Autodesk Fusion 360 part; units mm, degrees
(part 2 of 3)
sketch "web cuts" plane through (0, 0, -2.1) normal (0, 0, 1) x (1, 0, 0) in component "plate"
  line L0 (1.925, -17.125) -> (17.125, -17.125)
  line L1 (17.125, -17.125) -> (17.125, -1.925)
  line L2 (17.125, -1.925) -> (1.925, -1.925)
  line L3 (1.925, -1.925) -> (1.925, -17.125)
  line L4 (20.975, -17.125) -> (36.175, -17.125)
  line L5 (36.175, -17.125) -> (36.175, -1.925)
  line L6 (36.175, -1.925) -> (20.975, -1.925)
  line L7 (20.975, -1.925) -> (20.975, -17.125)
  line L8 (40.025, -17.125) -> (55.225, -17.125)
  line L9 (55.225, -17.125) -> (55.225, -1.925)
  line L10 (55.225, -1.925) -> (40.025, -1.925)
  line L11 (40.025, -1.925) -> (40.025, -17.125)
  line L12 (59.075, -17.125) -> (74.275, -17.125)
  line L13 (74.275, -17.125) -> (74.275, -1.925)
  line L14 (74.275, -1.925) -> (59.075, -1.925)
  line L15 (59.075, -1.925) -> (59.075, -17.125)
  line L16 (78.125, -17.125) -> (93.325, -17.125)
  line L17 (93.325, -17.125) -> (93.325, -1.925)
  line L18 (93.325, -1.925) -> (78.125, -1.925)
  line L19 (78.125, -1.925) -> (78.125, -17.125)
  line L20 (97.175, -17.125) -> (112.375, -17.125)
  line L21 (112.375, -17.125) -> (112.375, -1.925)
  line L22 (112.375, -1.925) -> (97.175, -1.925)
  line L23 (97.175, -1.925) -> (97.175, -17.125)
  line L24 (116.225, -17.125) -> (131.425, -17.125)
  line L25 (131.425, -17.125) -> (131.425, -1.925)
  line L26 (131.425, -1.925) -> (116.225, -1.925)
  line L27 (116.225, -1.925) -> (116.225, -17.125)
  line L28 (1.925, -36.175) -> (17.125, -36.175)
  line L29 (17.125, -36.175) -> (17.125, -20.975)
  line L30 (17.125, -20.975) -> (1.925, -20.975)
  line L31 (1.925, -20.975) -> (1.925, -36.175)
  line L32 (20.975, -36.175) -> (36.175, -36.175)
  line L33 (36.175, -36.175) -> (36.175, -20.975)
  line L34 (36.175, -20.975) -> (20.975, -20.975)
  line L35 (20.975, -20.975) -> (20.975, -36.175)
  line L36 (40.025, -36.175) -> (55.225, -36.175)
  line L37 (55.225, -36.175) -> (55.225, -20.975)
  line L38 (55.225, -20.975) -> (40.025, -20.975)
  line L39 (40.025, -20.975) -> (40.025, -36.175)
  line L40 (59.075, -36.175) -> (74.275, -36.175)
  line L41 (74.275, -36.175) -> (74.275, -20.975)
  line L42 (74.275, -20.975) -> (59.075, -20.975)
  line L43 (59.075, -20.975) -> (59.075, -36.175)
  line L44 (78.125, -36.175) -> (93.325, -36.175)
  line L45 (93.325, -36.175) -> (93.325, -20.975)
  line L46 (93.325, -20.975) -> (78.125, -20.975)
  line L47 (78.125, -20.975) -> (78.125, -36.175)
  line L48 (97.175, -36.175) -> (112.375, -36.175)
  line L49 (112.375, -36.175) -> (112.375, -20.975)
  line L50 (112.375, -20.975) -> (97.175, -20.975)
  line L51 (97.175, -20.975) -> (97.175, -36.175)
  line L52 (116.225, -36.175) -> (131.425, -36.175)
  line L53 (131.425, -36.175) -> (131.425, -20.975)
  line L54 (131.425, -20.975) -> (116.225, -20.975)
  line L55 (116.225, -20.975) -> (116.225, -36.175)
  line L56 (6.688, -55.225) -> (21.888, -55.225)
  line L57 (21.888, -55.225) -> (21.888, -40.025)
  line L58 (21.888, -40.025) -> (6.688, -40.025)
  line L59 (6.688, -40.025) -> (6.688, -55.225)
  line L60 (30.5, -55.225) -> (45.7, -55.225)
  line L61 (45.7, -55.225) -> (45.7, -40.025)
  line L62 (45.7, -40.025) -> (30.5, -40.025)
  line L63 (30.5, -40.025) -> (30.5, -55.225)
  line L64 (49.55, -55.225) -> (64.75, -55.225)
  line L65 (64.75, -55.225) -> (64.75, -40.025)
  line L66 (64.75, -40.025) -> (49.55, -40.025)
  line L67 (49.55, -40.025) -> (49.55, -55.225)
  line L68 (68.6, -55.225) -> (83.8, -55.225)
  line L69 (83.8, -55.225) -> (83.8, -40.025)
  line L70 (83.8, -40.025) -> (68.6, -40.025)
  line L71 (68.6, -40.025) -> (68.6, -55.225)
  line L72 (87.65, -55.225) -> (102.85, -55.225)
  line L73 (102.85, -55.225) -> (102.85, -40.025)
  line L74 (102.85, -40.025) -> (87.65, -40.025)
  line L75 (87.65, -40.025) -> (87.65, -55.225)
  line L76 (106.7, -55.225) -> (121.9, -55.225)
  line L77 (121.9, -55.225) -> (121.9, -40.025)
  line L78 (121.9, -40.025) -> (106.7, -40.025)
  line L79 (106.7, -40.025) -> (106.7, -55.225)
  line L80 (9.069, -74.275) -> (24.269, -74.275)
  line L81 (24.269, -74.275) -> (24.269, -59.075)
  line L82 (24.269, -59.075) -> (9.069, -59.075)
  line L83 (9.069, -59.075) -> (9.069, -74.275)
  line L84 (35.263, -74.275) -> (50.463, -74.275)
  line L85 (50.463, -74.275) -> (50.463, -59.075)
  line L86 (50.463, -59.075) -> (35.263, -59.075)
  line L87 (35.263, -59.075) -> (35.263, -74.275)
  line L88 (54.313, -74.275) -> (69.513, -74.275)
  line L89 (69.513, -74.275) -> (69.513, -59.075)
  line L90 (69.513, -59.075) -> (54.313, -59.075)
  line L91 (54.313, -59.075) -> (54.313, -74.275)
  line L92 (73.363, -74.275) -> (88.563, -74.275)
  line L93 (88.563, -74.275) -> (88.563, -59.075)
  line L94 (88.563, -59.075) -> (73.363, -59.075)
  line L95 (73.363, -59.075) -> (73.363, -74.275)
  line L96 (92.413, -74.275) -> (107.613, -74.275)
  line L97 (107.613, -74.275) -> (107.613, -59.075)
  line L98 (107.613, -59.075) -> (92.413, -59.075)
  line L99 (92.413, -59.075) -> (92.413, -74.275)
  line L100 (111.462, -74.275) -> (126.662, -74.275)
  line L101 (126.662, -74.275) -> (126.662, -59.075)
  line L102 (126.662, -59.075) -> (111.462, -59.075)
  line L103 (111.462, -59.075) -> (111.462, -74.275)
  line L104 (13.831, -93.325) -> (29.031, -93.325)
  line L105 (29.031, -93.325) -> (29.031, -78.125)
  line L106 (29.031, -78.125) -> (13.831, -78.125)
  line L107 (13.831, -78.125) -> (13.831, -93.325)
  line L108 (4.993, -94.925) -> (13.993, -94.925)
  line L109 (13.993, -94.925) -> (13.993, -77.525)
  line L110 (13.993, -77.525) -> (4.993, -77.525)
  line L111 (4.993, -77.525) -> (4.993, -94.925)
  line L112 (28.869, -94.925) -> (37.869, -94.925)
  line L113 (37.869, -94.925) -> (37.869, -77.525)
  line L114 (37.869, -77.525) -> (28.869, -77.525)
  line L115 (28.869, -77.525) -> (28.869, -94.925)
  line L116 (44.788, -93.325) -> (59.988, -93.325)
  line L117 (59.988, -93.325) -> (59.988, -78.125)
  line L118 (59.988, -78.125) -> (44.788, -78.125)
  line L119 (44.788, -78.125) -> (44.788, -93.325)
  line L120 (63.838, -93.325) -> (79.038, -93.325)
  line L121 (79.038, -93.325) -> (79.038, -78.125)
  line L122 (79.038, -78.125) -> (63.838, -78.125)
  line L123 (63.838, -78.125) -> (63.838, -93.325)
  line L124 (82.887, -93.325) -> (98.087, -93.325)
  line L125 (98.087, -93.325) -> (98.087, -78.125)
  line L126 (98.087, -78.125) -> (82.887, -78.125)
  line L127 (82.887, -78.125) -> (82.887, -93.325)
  line L128 (101.938, -93.325) -> (117.138, -93.325)
  line L129 (117.138, -93.325) -> (117.138, -78.125)
  line L130 (117.138, -78.125) -> (101.938, -78.125)
  line L131 (101.938, -78.125) -> (101.938, -93.325)
  line L132 (120.988, -93.325) -> (136.188, -93.325)
  line L133 (136.188, -93.325) -> (136.188, -78.125)
  line L134 (136.188, -78.125) -> (120.988, -78.125)
  line L135 (120.988, -78.125) -> (120.988, -93.325)
  line L136 (13.831, -112.375) -> (29.031, -112.375)
  line L137 (29.031, -112.375) -> (29.031, -97.175)
  line L138 (29.031, -97.175) -> (13.831, -97.175)
  line L139 (13.831, -97.175) -> (13.831, -112.375)
  line L140 (37.644, -112.375) -> (52.844, -112.375)
  line L141 (52.844, -112.375) -> (52.844, -97.175)
  line L142 (52.844, -97.175) -> (37.644, -97.175)
  line L143 (37.644, -97.175) -> (37.644, -112.375)
  line L144 (61.456, -112.375) -> (76.656, -112.375)
  line L145 (76.656, -112.375) -> (76.656, -97.175)
  line L146 (76.656, -97.175) -> (61.456, -97.175)
  line L147 (61.456, -97.175) -> (61.456, -112.375)
  line L148 (82.887, -112.375) -> (98.087, -112.375)
  line L149 (98.087, -112.375) -> (98.087, -97.175)
  line L150 (98.087, -97.175) -> (82.887, -97.175)
  line L151 (82.887, -97.175) -> (82.887, -112.375)
  line L152 (101.938, -112.375) -> (117.138, -112.375)
  line L153 (117.138, -112.375) -> (117.138, -97.175)
  line L154 (117.138, -97.175) -> (101.938, -97.175)
  line L155 (101.938, -97.175) -> (101.938, -112.375)
  line L156 (120.988, -112.375) -> (136.188, -112.375)
  line L157 (136.188, -112.375) -> (136.188, -97.175)
  line L158 (136.188, -97.175) -> (120.988, -97.175)
  line L159 (120.988, -97.175) -> (120.988, -112.375)
  line L160 (145.325, -36.895) -> (154.125, -36.895)
  line L161 (162.125, -28.895) -> (162.125, 5)
  line L162 (154.125, 13) -> (145.325, 13)
  line L163 (137.325, 5) -> (137.325, -28.895)
  arc A0 (154.125, -36.895) -> (162.125, -28.895) centre (154.125, -28.895) ccw
  arc A1 (162.125, 5) -> (154.125, 13) centre (154.125, 5) ccw
  arc A2 (145.325, 13) -> (137.325, 5) centre (145.325, 5) ccw
  arc A3 (137.325, -28.895) -> (145.325, -36.895) centre (145.325, -28.895) ccw
  circle A4 centre (16, -19.05) radius 3.3
  circle A5 centre (56.5, -19.05) radius 3.3
  circle A6 centre (100.5, -19.05) radius 3.3
  circle A7 centre (132, -19.05) radius 3.3
  circle A8 centre (17, -95.25) radius 3.3
  circle A9 centre (58.5, -95.25) radius 3.3
  circle A10 centre (99.5, -95.25) radius 3.3
  circle A11 centre (142.5, -95.25) radius 3.3
  dimension "d2473" = 6.6
  dimension "d2474" = 6.6
  dimension "d2475" = 6.6
  dimension "d2476" = 6.6
  dimension "d2477" = 6.6
  dimension "d2478" = 6.6
  dimension "d2479" = 6.6
  dimension "d2480" = 6.6
  constraint coincident L0.end L1.start
  constraint coincident L1.end L2.start
  constraint coincident L2.end L3.start
  constraint coincident L0.start L3.end
  constraint coincident L4.end L5.start
  constraint coincident L5.end L6.start
  constraint coincident L6.end L7.start
  constraint coincident L4.start L7.end
  constraint coincident L8.end L9.start
  constraint coincident L9.end L10.start
  constraint coincident L10.end L11.start
  constraint coincident L8.start L11.end
  constraint coincident L12.end L13.start
  constraint coincident L13.end L14.start
  constraint coincident L14.end L15.start
  constraint coincident L12.start L15.end
  constraint coincident L16.end L17.start
  constraint coincident L17.end L18.start
  constraint coincident L18.end L19.start
  constraint coincident L16.start L19.end
  constraint coincident L20.end L21.start
  constraint coincident L21.end L22.start
  constraint coincident L22.end L23.start
  constraint coincident L20.start L23.end
  constraint coincident L24.end L25.start
  constraint coincident L25.end L26.start
  constraint coincident L26.end L27.start
  constraint coincident L24.start L27.end
  constraint coincident L28.end L29.start
  constraint coincident L29.end L30.start
  constraint coincident L30.end L31.start
  constraint coincident L28.start L31.end
  constraint coincident L32.end L33.start
  constraint coincident L33.end L34.start
  constraint coincident L34.end L35.start
  constraint coincident L32.start L35.end
  constraint coincident L36.end L37.start
  constraint coincident L37.end L38.start
  constraint coincident L38.end L39.start
  constraint coincident L36.start L39.end
  constraint coincident L40.end L41.start
  constraint coincident L41.end L42.start
  constraint coincident L42.end L43.start
  constraint coincident L40.start L43.end
  constraint coincident L44.end L45.start
  constraint coincident L45.end L46.start
  constraint coincident L46.end L47.start
  constraint coincident L44.start L47.end
  constraint coincident L48.end L49.start
  constraint coincident L49.end L50.start
  constraint coincident L50.end L51.start
  constraint coincident L48.start L51.end
  constraint coincident L52.end L53.start
  constraint coincident L53.end L54.start
  constraint coincident L54.end L55.start
  constraint coincident L52.start L55.end
  constraint coincident L56.end L57.start
  constraint coincident L57.end L58.start
  constraint coincident L58.end L59.start
  constraint coincident L56.start L59.end
  constraint coincident L60.end L61.start
  constraint coincident L61.end L62.start
  constraint coincident L62.end L63.start
  constraint coincident L60.start L63.end
  constraint coincident L64.end L65.start
  constraint coincident L65.end L66.start
  constraint coincident L66.end L67.start
  constraint coincident L64.start L67.end
  constraint coincident L68.end L69.start
  constraint coincident L69.end L70.start
  constraint coincident L70.end L71.start
  constraint coincident L68.start L71.end
  constraint coincident L72.end L73.start
  constraint coincident L73.end L74.start
  constraint coincident L74.end L75.start
  constraint coincident L72.start L75.end
  constraint coincident L76.end L77.start
  constraint coincident L77.end L78.start
  constraint coincident L78.end L79.start
  constraint coincident L76.start L79.end
  constraint coincident L80.end L81.start
  constraint coincident L81.end L82.start
  constraint coincident L82.end L83.start
  constraint coincident L80.start L83.end
  constraint coincident L84.end L85.start
  constraint coincident L85.end L86.start
  constraint coincident L86.end L87.start
  constraint coincident L84.start L87.end
  constraint coincident L88.end L89.start
  constraint coincident L89.end L90.start
  constraint coincident L90.end L91.start
  constraint coincident L88.start L91.end
  constraint coincident L92.end L93.start
  constraint coincident L93.end L94.start
  constraint coincident L94.end L95.start
  constraint coincident L92.start L95.end
  constraint coincident L96.end L97.start
  constraint coincident L97.end L98.start
  constraint coincident L98.end L99.start
  constraint coincident L96.start L99.end
  constraint coincident L100.end L101.start
  constraint coincident L101.end L102.start
  constraint coincident L102.end L103.start
  constraint coincident L100.start L103.end
  constraint coincident L104.end L105.start
  constraint coincident L105.end L106.start
  constraint coincident L106.end L107.start
  constraint coincident L104.start L107.end
  constraint coincident L108.end L109.start
  constraint coincident L109.end L110.start
  constraint coincident L110.end L111.start
  constraint coincident L108.start L111.end
  constraint coincident L112.end L113.start
  constraint coincident L113.end L114.start
  constraint coincident L114.end L115.start
  constraint coincident L112.start L115.end
  constraint coincident L116.end L117.start
  constraint coincident L117.end L118.start
  constraint coincident L118.end L119.start
  constraint coincident L116.start L119.end
  constraint coincident L120.end L121.start
  constraint coincident L121.end L122.start
  constraint coincident L122.end L123.start
  constraint coincident L120.start L123.end
  constraint coincident L124.end L125.start
  constraint coincident L125.end L126.start
  constraint coincident L126.end L127.start
  constraint coincident L124.start L127.end
  constraint coincident L128.end L129.start
  constraint coincident L129.end L130.start
  constraint coincident L130.end L131.start
  constraint coincident L128.start L131.end
  constraint coincident L132.end L133.start
  constraint coincident L133.end L134.start
  constraint coincident L134.end L135.start
  constraint coincident L132.start L135.end
  constraint coincident L136.end L137.start
  constraint coincident L137.end L138.start
  constraint coincident L138.end L139.start
  constraint coincident L136.start L139.end
  constraint coincident L140.end L141.start
  constraint coincident L141.end L142.start
  constraint coincident L142.end L143.start
  constraint coincident L140.start L143.end
  constraint coincident L144.end L145.start
  constraint coincident L145.end L146.start
  constraint coincident L146.end L147.start
  constraint coincident L144.start L147.end
  constraint coincident L148.end L149.start
  constraint coincident L149.end L150.start
  constraint coincident L150.end L151.start
  constraint coincident L148.start L151.end
  constraint coincident L152.end L153.start
  constraint coincident L153.end L154.start
  constraint coincident L154.end L155.start
  constraint coincident L152.start L155.end
  constraint coincident L156.end L157.start
  constraint coincident L157.end L158.start
  constraint coincident L158.end L159.start
  constraint coincident L156.start L159.end
  measures "d2473" diameter of A4
  measures "d2474" diameter of A5
  measures "d2475" diameter of A6
  measures "d2476" diameter of A7
  measures "d2477" diameter of A8
  measures "d2478" diameter of A9
  measures "d2479" diameter of A10
  measures "d2480" diameter of A11
extrude "Extrude4'" cut sketch "web cuts" along normal blind 2.2 bodies 3 in component "plate"
combine "Combine1" operation add target body 2 tool bodies 3 in component "plate"
sketch "plate bosses" plane through (0, 0, 0) normal (0, 0, 1) x (1, 0, 0) in component "plate"
  circle A0 centre (-5.0104, -119.3104) radius 2.8
  circle A1 centre (160.1354, -119.3104) radius 2.8
  circle A2 centre (49.2083, 13.5) radius 2.8
  circle A3 centre (49.2083, -121.8) radius 2.8
  circle A4 centre (105.9167, 13.5) radius 2.8
  circle A5 centre (105.9167, -121.8) radius 2.8
  circle A6 centre (-7.5, -54.15) radius 2.8
  circle A7 centre (162.625, -54.15) radius 2.8
  circle A8 centre (19.1438, 13.5) radius 2.8
  circle A9 centre (-7.5, -13.1438) radius 2.8
  dimension "d2483" = 5.6
  dimension "d2484" = 5.6
  dimension "d2485" = 5.6
  dimension "d2486" = 5.6
  dimension "d2487" = 5.6
  dimension "d2488" = 5.6
  dimension "d2489" = 5.6
  dimension "d2490" = 5.6
  dimension "d2491" = 5.6
  dimension "d2492" = 5.6
  measures "d2483" diameter of A0
  measures "d2484" diameter of A1
  measures "d2485" diameter of A2
  measures "d2486" diameter of A3
  measures "d2487" diameter of A4
  measures "d2488" diameter of A5
  measures "d2489" diameter of A6
  measures "d2490" diameter of A7
  measures "d2491" diameter of A8
  measures "d2492" diameter of A9
extrude "Extrude5'" add sketch "plate bosses" against normal blind 3 bodies 2 in component "plate"
sketch "inserts" plane through (0, 0, 0) normal (0, 0, 1) x (1, 0, 0) in component "plate"
  circle A0 centre (-5.0104, -119.3104) radius 1.6
  circle A1 centre (160.1354, -119.3104) radius 1.6
  circle A2 centre (49.2083, 13.5) radius 1.6
  circle A3 centre (49.2083, -121.8) radius 1.6
  circle A4 centre (105.9167, 13.5) radius 1.6
  circle A5 centre (105.9167, -121.8) radius 1.6
  circle A6 centre (-7.5, -54.15) radius 1.6
  circle A7 centre (162.625, -54.15) radius 1.6
  circle A8 centre (19.1438, 13.5) radius 1.6
  circle A9 centre (-7.5, -13.1438) radius 1.6
  dimension "d2495" = 3.2
  dimension "d2496" = 3.2
  dimension "d2497" = 3.2
  dimension "d2498" = 3.2
  dimension "d2499" = 3.2
  dimension "d2500" = 3.2
  dimension "d2501" = 3.2
  dimension "d2502" = 3.2
  dimension "d2503" = 3.2
  dimension "d2504" = 3.2
  measures "d2495" diameter of A0
  measures "d2496" diameter of A1
  measures "d2497" diameter of A2
  measures "d2498" diameter of A3
  measures "d2499" diameter of A4
  measures "d2500" diameter of A5
  measures "d2501" diameter of A6
  measures "d2502" diameter of A7
  measures "d2503" diameter of A8
  measures "d2504" diameter of A9
extrude "Extrude6'" cut sketch "inserts" against normal blind 3.01 bodies 2 in component "plate"
sketch "rim" plane through (0, 0, 0) normal (0, 0, 1) x (1, 0, 0) in component "wheel"
  spline S0 degree 5 poles (16.6, 4) (16.6, 4.0196) (16.5988, 4.0588) (16.5932, 4.1175) (16.5787, 4.1954) (16.5497, 4.2915) (16.5116, 4.3858) (16.4664, 4.4782) (16.416, 4.5686) (16.3623, 4.6574) (16.3071, 4.7453) (16.252, 4.8329) (16.1989, 4.9209) (16.1495, 5.01) (16.106, 5.1006) (16.0704, 5.1928) (16.0444, 5.2866) (16.0293, 5.3818) (16.0255, 5.4781) (16.0327, 5.5751) (16.0497, 5.6725) (16.0747, 5.7698) (16.1057, 5.8669) (16.1406, 5.9636) (16.1776, 6.0602) (16.2146, 6.1572) (16.25, 6.2547) (16.2817, 6.3532) (16.3081, 6.4526) (16.327, 6.5526) (16.3367, 6.6525) (16.3355, 6.7516) (16.3225, 6.8489) (16.2973, 6.9439) (16.2604, 7.0358) (16.2133, 7.1244) (16.1575, 7.2095) (16.0951, 7.2913) (16.0281, 7.3701) (15.9581, 7.4467) (15.8868, 7.5221) (15.8157, 7.5973) (15.7464, 7.6733) (15.6806, 7.751) (15.6203, 7.8314) (15.5673, 7.9149) (15.5235, 8.0018) (15.4901, 8.0922) (15.4677, 8.1859) (15.4558, 8.2825) (15.4534, 8.3813) (15.459, 8.4817) (15.4705, 8.5829) (15.4859, 8.6846) (15.5032, 8.7865) (15.5207, 8.8888) (15.5363, 8.9914) (15.5482, 9.0942) (15.5547, 9.1969) (15.5537, 9.2986) (15.5437, 9.3985) (15.5233, 9.4954) (15.4915, 9.5884) (15.4482, 9.6766) (15.3942, 9.7596) (15.3306, 9.8372) (15.2593, 9.9098) (15.1822, 9.9779) (15.1011, 10.0421) (15.0175, 10.1036) (14.9328, 10.1636) (14.8484, 10.2235) (14.7656, 10.2845) (14.6859, 10.3479) (14.6111, 10.415) (14.5429, 10.4865) (14.483, 10.5632) (14.4326, 10.6453) (14.3923, 10.7329) (14.3618, 10.8253) (14.3402, 10.9218) (14.326, 11.0213) (14.3176, 11.1228) (14.3128, 11.2255) (14.31, 11.3289) (14.3071, 11.4327) (14.3024, 11.5363) (14.2941, 11.6395) (14.2803, 11.7414) (14.2596, 11.841) (14.2303, 11.937) (14.1913, 12.0281) (14.142, 12.113) (14.0824, 12.1911) (14.0132, 12.262) (13.9357, 12.3258) (13.8516, 12.3831) (13.7627, 12.4347) (13.6706, 12.4819) (13.5766, 12.5259) (13.4819, 12.5683) (13.3874, 12.6105) (13.2943, 12.6542) (13.2038, 12.7009) (13.1173, 12.752) (13.0364, 12.8089) (12.9627, 12.8724) (12.8972, 12.9431) (12.8406, 13.0212) (12.7927, 13.1059) (12.7527, 13.1962) (12.7194, 13.291) (12.6913, 13.3889) (12.6666, 13.4888) (12.6436, 13.5897) (12.6206, 13.6908) (12.5957, 13.7916) (12.5674, 13.8911) (12.5341, 13.9884) (12.4943, 14.0821) (12.4469, 14.1705) (12.3909, 14.2522) (12.326, 14.326) (12.2522, 14.3909) (12.1705, 14.4469) (12.0821, 14.4943) (11.9884, 14.5341) (11.8911, 14.5674) (11.7916, 14.5957) (11.6908, 14.6206) (11.5897, 14.6436) (11.4888, 14.6666) (11.3889, 14.6913) (11.291, 14.7194) (11.1962, 14.7527) (11.1059, 14.7927) (11.0212, 14.8406) (10.9431, 14.8972) (10.8724, 14.9627) (10.8089, 15.0364) (10.752, 15.1173) (10.7009, 15.2038) (10.6542, 15.2943) (10.6105, 15.3874) (10.5683, 15.4819) (10.5259, 15.5766) (10.4819, 15.6706) (10.4347, 15.7627) (10.3831, 15.8516) (10.3258, 15.9357) (10.262, 16.0132) (10.1911, 16.0824) (10.113, 16.142) (10.0281, 16.1913) (9.937, 16.2303) (9.841, 16.2596) (9.7414, 16.2803) (9.6395, 16.2941) (9.5363, 16.3024) (9.4327, 16.3071) (9.3289, 16.31) (9.2255, 16.3128) (9.1228, 16.3176) (9.0213, 16.326) (8.9218, 16.3402) (8.8253, 16.3618) (8.7329, 16.3923) (8.6453, 16.4326) (8.5632, 16.483) (8.4865, 16.5429) (8.415, 16.6111) (8.3479, 16.6859) (8.2845, 16.7656) (8.2235, 16.8484) (8.1636, 16.9328) (8.1036, 17.0175) (8.0421, 17.1011) (7.9779, 17.1822) (7.9098, 17.2593) (7.8372, 17.3306) (7.7596, 17.3942) (7.6766, 17.4482) (7.5884, 17.4915) (7.4954, 17.5233) (7.3985, 17.5437) (7.2986, 17.5537) (7.1969, 17.5547) (7.0942, 17.5482) (6.9914, 17.5363) (6.8888, 17.5207) (6.7865, 17.5032) (6.6846, 17.4859) (6.5829, 17.4705) (6.4817, 17.459) (6.3813, 17.4534) (6.2825, 17.4558) (6.1859, 17.4677) (6.0922, 17.4901) (6.0018, 17.5235) (5.9149, 17.5673) (5.8314, 17.6203) (5.751, 17.6806) (5.6733, 17.7464) (5.5973, 17.8157) (5.5221, 17.8868) (5.4467, 17.9581) (5.3701, 18.0281) (5.2913, 18.0951) (5.2095, 18.1575) (5.1244, 18.2133) (5.0358, 18.2604) (4.9439, 18.2973) (4.8489, 18.3225) (4.7516, 18.3355) (4.6525, 18.3367) (4.5526, 18.327) (4.4526, 18.3081) (4.3532, 18.2817) (4.2547, 18.25) (4.1572, 18.2146) (4.0602, 18.1776) (3.9636, 18.1406) (3.8669, 18.1057) (3.7698, 18.0747) (3.6725, 18.0497) (3.5751, 18.0327) (3.4781, 18.0255) (3.3818, 18.0293) (3.2866, 18.0444) (3.1928, 18.0704) (3.1006, 18.106) (3.01, 18.1495) (2.9209, 18.1989) (2.8329, 18.252) (2.7453, 18.3071) (2.6574, 18.3623) (2.5686, 18.416) (2.4782, 18.4664) (2.3858, 18.5116) (2.2915, 18.5497) (2.1954, 18.5787) (2.098, 18.5969) (2, 18.6031) (1.902, 18.5969) (1.8046, 18.5787) (1.7085, 18.5497) (1.6142, 18.5116) (1.5218, 18.4664) (1.4314, 18.416) (1.3426, 18.3623) (1.2547, 18.3071) (1.1671, 18.252) (1.0791, 18.1989) (0.99, 18.1495) (0.8994, 18.106) (0.8072, 18.0704) (0.7134, 18.0444) (0.6182, 18.0293) (0.5219, 18.0255) (0.4249, 18.0327) (0.3275, 18.0497) (0.2302, 18.0747) (0.1331, 18.1057) (0.0364, 18.1406) (-0.0602, 18.1776) (-0.1572, 18.2146) (-0.2547, 18.25) (-0.3532, 18.2817) (-0.4526, 18.3081) (-0.5526, 18.327) (-0.6525, 18.3367) (-0.7516, 18.3355) (-0.8489, 18.3225) (-0.9439, 18.2973) (-1.0358, 18.2604) (-1.1244, 18.2133) (-1.2095, 18.1575) (-1.2913, 18.0951) (-1.3701, 18.0281) (-1.4467, 17.9581) (-1.5221, 17.8868) (-1.5973, 17.8157) (-1.6733, 17.7464) (-1.751, 17.6806) (-1.8314, 17.6203) (-1.9149, 17.5673) (-2.0018, 17.5235) (-2.0922, 17.4901) (-2.1859, 17.4677) (-2.2825, 17.4558) (-2.3813, 17.4534) (-2.4817, 17.459) (-2.5829, 17.4705) (-2.6846, 17.4859) (-2.7865, 17.5032) (-2.8888, 17.5207) (-2.9914, 17.5363) (-3.0942, 17.5482) (-3.1969, 17.5547) (-3.2986, 17.5537) (-3.3985, 17.5437) (-3.4954, 17.5233) (-3.5884, 17.4915) (-3.6766, 17.4482) (-3.7596, 17.3942) (-3.8372, 17.3306) (-3.9098, 17.2593) (-3.9779, 17.1822) (-4.0421, 17.1011) (-4.1036, 17.0175) (-4.1636, 16.9328) (-4.2235, 16.8484) (-4.2845, 16.7656) (-4.3479, 16.6859) (-4.415, 16.6111) (-4.4865, 16.5429) (-4.5632, 16.483) (-4.6453, 16.4326) (-4.7329, 16.3923) (-4.8253, 16.3618) (-4.9218, 16.3402) (-5.0213, 16.326) (-5.1228, 16.3176) (-5.2255, 16.3128) (-5.3289, 16.31) (-5.4327, 16.3071) (-5.5363, 16.3024) (-5.6395, 16.2941) (-5.7414, 16.2803) (-5.841, 16.2596) (-5.937, 16.2303) (-6.0281, 16.1913) (-6.113, 16.142) (-6.1911, 16.0824) (-6.262, 16.0132) (-6.3258, 15.9357) (-6.3831, 15.8516) (-6.4347, 15.7627) (-6.4819, 15.6706) (-6.5259, 15.5766) (-6.5683, 15.4819) (-6.6105, 15.3874) (-6.6542, 15.2943) (-6.7009, 15.2038) (-6.752, 15.1173) (-6.8089, 15.0364) (-6.8724, 14.9627) (-6.9431, 14.8972) (-7.0212, 14.8406) (-7.1059, 14.7927) (-7.1962, 14.7527) (-7.291, 14.7194) (-7.3889, 14.6913) (-7.4888, 14.6666) (-7.5897, 14.6436) (-7.6908, 14.6206) (-7.7916, 14.5957) (-7.8911, 14.5674) (-7.9884, 14.5341) (-8.0821, 14.4943) (-8.1705, 14.4469) (-8.2522, 14.3909) (-8.326, 14.326) (-8.3909, 14.2522) (-8.4469, 14.1705) (-8.4943, 14.0821) (-8.5341, 13.9884) (-8.5674, 13.8911) (-8.5957, 13.7916) (-8.6206, 13.6908) (-8.6436, 13.5897) (-8.6666, 13.4888) (-8.6913, 13.3889) (-8.7194, 13.291) (-8.7527, 13.1962) (-8.7927, 13.1059) (-8.8406, 13.0212) (-8.8972, 12.9431) (-8.9627, 12.8724) (-9.0364, 12.8089) (-9.1173, 12.752) (-9.2038, 12.7009) (-9.2943, 12.6542) (-9.3874, 12.6105) (-9.4819, 12.5683) (-9.5766, 12.5259) (-9.6706, 12.4819) (-9.7627, 12.4347) (-9.8516, 12.3831) (-9.9357, 12.3258) (-10.0132, 12.262) (-10.0824, 12.1911) (-10.142, 12.113) (-10.1913, 12.0281) (-10.2303, 11.937) (-10.2596, 11.841) (-10.2803, 11.7414) (-10.2941, 11.6395) (-10.3024, 11.5363) (-10.3071, 11.4327) (-10.31, 11.3289) (-10.3128, 11.2255) (-10.3176, 11.1228) (-10.326, 11.0213) (-10.3402, 10.9218) (-10.3618, 10.8253) (-10.3923, 10.7329) (-10.4326, 10.6453) (-10.483, 10.5632) (-10.5429, 10.4865) (-10.6111, 10.415) (-10.6859, 10.3479) (-10.7656, 10.2845) (-10.8484, 10.2235) (-10.9328, 10.1636) (-11.0175, 10.1036) (-11.1011, 10.0421) (-11.1822, 9.9779) (-11.2593, 9.9098) (-11.3306, 9.8372) (-11.3942, 9.7596) (-11.4482, 9.6766) (-11.4915, 9.5884) (-11.5233, 9.4954) (-11.5437, 9.3985) (-11.5537, 9.2986) (-11.5547, 9.1969) (-11.5482, 9.0942) (-11.5363, 8.9914) (-11.5207, 8.8888) (-11.5032, 8.7865) (-11.4859, 8.6846) (-11.4705, 8.5829) (-11.459, 8.4817) (-11.4534, 8.3813) (-11.4558, 8.2825) (-11.4677, 8.1859) (-11.4901, 8.0922) (-11.5235, 8.0018) (-11.5673, 7.9149) (-11.6203, 7.8314) (-11.6806, 7.751) (-11.7464, 7.6733) (-11.8157, 7.5973) (-11.8868, 7.5221) (-11.9581, 7.4467) (-12.0281, 7.3701) (-12.0951, 7.2913) (-12.1575, 7.2095) (-12.2133, 7.1244) (-12.2604, 7.0358) (-12.2973, 6.9439) (-12.3225, 6.8489) (-12.3355, 6.7516) (-12.3367, 6.6525) (-12.327, 6.5526) (-12.3081, 6.4526) (-12.2817, 6.3532) (-12.25, 6.2547) (-12.2146, 6.1572) (-12.1776, 6.0602) (-12.1406, 5.9636) (-12.1057, 5.8669) (-12.0747, 5.7698) (-12.0497, 5.6725) (-12.0327, 5.5751) (-12.0255, 5.4781) (-12.0293, 5.3818) (-12.0444, 5.2866) (-12.0704, 5.1928) (-12.106, 5.1006) (-12.1495, 5.01) (-12.1989, 4.9209) (-12.252, 4.8329) (-12.3071, 4.7453) (-12.3623, 4.6574) (-12.416, 4.5686) (-12.4664, 4.4782) (-12.5116, 4.3858) (-12.5497, 4.2915) (-12.5787, 4.1954) (-12.5969, 4.098) (-12.6031, 4) (-12.5969, 3.902) (-12.5787, 3.8046) (-12.5497, 3.7085) (-12.5116, 3.6142) (-12.4664, 3.5218) (-12.416, 3.4314) (-12.3623, 3.3426) (-12.3071, 3.2547) (-12.252, 3.1671) (-12.1989, 3.0791) (-12.1495, 2.99) (-12.106, 2.8994) (-12.0704, 2.8072) (-12.0444, 2.7134) (-12.0293, 2.6182) (-12.0255, 2.5219) (-12.0327, 2.4249) (-12.0497, 2.3275) (-12.0747, 2.2302) (-12.1057, 2.1331) (-12.1406, 2.0364) (-12.1776, 1.9398) (-12.2146, 1.8428) (-12.25, 1.7453) (-12.2817, 1.6468) (-12.3081, 1.5474) (-12.327, 1.4474) (-12.3367, 1.3475) (-12.3355, 1.2484) (-12.3225, 1.1511) (-12.2973, 1.0561) (-12.2604, 0.9642) (-12.2133, 0.8756) (-12.1575, 0.7905) (-12.0951, 0.7087) (-12.0281, 0.6299) (-11.9581, 0.5533) (-11.8868, 0.4779) (-11.8157, 0.4027) (-11.7464, 0.3267) (-11.6806, 0.249) (-11.6203, 0.1686) (-11.5673, 0.0851) (-11.5235, -0.0018) (-11.4901, -0.0922) (-11.4677, -0.1859) (-11.4558, -0.2825) (-11.4534, -0.3813) (-11.459, -0.4817) (-11.4705, -0.5829) (-11.4859, -0.6846) (-11.5032, -0.7865) (-11.5207, -0.8888) (-11.5363, -0.9914) (-11.5482, -1.0942) (-11.5547, -1.1969) (-11.5537, -1.2986) (-11.5437, -1.3985) (-11.5233, -1.4954) (-11.4915, -1.5884) (-11.4482, -1.6766) (-11.3942, -1.7596) (-11.3306, -1.8372) (-11.2593, -1.9098) (-11.1822, -1.9779) (-11.1011, -2.0421) (-11.0175, -2.1036) (-10.9328, -2.1636) (-10.8484, -2.2235) (-10.7656, -2.2845) (-10.6859, -2.3479) (-10.6111, -2.415) (-10.5429, -2.4865) (-10.483, -2.5632) (-10.4326, -2.6453) (-10.3923, -2.7329) (-10.3618, -2.8253) (-10.3402, -2.9218) (-10.326, -3.0213) (-10.3176, -3.1228) (-10.3128, -3.2255) (-10.31, -3.3289) (-10.3071, -3.4327) (-10.3024, -3.5363) (-10.2941, -3.6395) (-10.2803, -3.7414) (-10.2596, -3.841) (-10.2303, -3.937) (-10.1913, -4.0281) (-10.142, -4.113) (-10.0824, -4.1911) (-10.0132, -4.262) (-9.9357, -4.3258) (-9.8516, -4.3831) (-9.7627, -4.4347) (-9.6706, -4.4819) (-9.5766, -4.5259) (-9.4819, -4.5683) (-9.3874, -4.6105) (-9.2943, -4.6542) (-9.2038, -4.7009) (-9.1173, -4.752) (-9.0364, -4.8089) (-8.9627, -4.8724) (-8.8972, -4.9431) (-8.8406, -5.0212) (-8.7927, -5.1059) (-8.7527, -5.1962) (-8.7194, -5.291) (-8.6913, -5.3889) (-8.6666, -5.4888) (-8.6436, -5.5897) (-8.6206, -5.6908) (-8.5957, -5.7916) (-8.5674, -5.8911) (-8.5341, -5.9884) (-8.4943, -6.0821) (-8.4469, -6.1705) (-8.3909, -6.2522) (-8.326, -6.326) (-8.2522, -6.3909) (-8.1705, -6.4469) (-8.0821, -6.4943) (-7.9884, -6.5341) (-7.8911, -6.5674) (-7.7916, -6.5957) (-7.6908, -6.6206) (-7.5897, -6.6436) (-7.4888, -6.6666) (-7.3889, -6.6913) (-7.291, -6.7194) (-7.1962, -6.7527) (-7.1059, -6.7927) (-7.0212, -6.8406) (-6.9431, -6.8972) (-6.8724, -6.9627) (-6.8089, -7.0364) (-6.752, -7.1173) (-6.7009, -7.2038) (-6.6542, -7.2943) (-6.6105, -7.3874) (-6.5683, -7.4819) (-6.5259, -7.5766) (-6.4819, -7.6706) (-6.4347, -7.7627) (-6.3831, -7.8516) (-6.3258, -7.9357) (-6.262, -8.0132) (-6.1911, -8.0824) (-6.113, -8.142) (-6.0281, -8.1913) (-5.937, -8.2303) (-5.841, -8.2596) (-5.7414, -8.2803) (-5.6395, -8.2941) (-5.5363, -8.3024) (-5.4327, -8.3071) (-5.3289, -8.31) (-5.2255, -8.3128) (-5.1228, -8.3176) (-5.0213, -8.326) (-4.9218, -8.3402) (-4.8253, -8.3618) (-4.7329, -8.3923) (-4.6453, -8.4326) (-4.5632, -8.483) (-4.4865, -8.5429) (-4.415, -8.6111) (-4.3479, -8.6859) (-4.2845, -8.7656) (-4.2235, -8.8484) (-4.1636, -8.9328) (-4.1036, -9.0175) (-4.0421, -9.1011) (-3.9779, -9.1822) (-3.9098, -9.2593) (-3.8372, -9.3306) (-3.7596, -9.3942) (-3.6766, -9.4482) (-3.5884, -9.4915) (-3.4954, -9.5233) (-3.3985, -9.5437) (-3.2986, -9.5537) (-3.1969, -9.5547) (-3.0942, -9.5482) (-2.9914, -9.5363) (-2.8888, -9.5207) (-2.7865, -9.5032) (-2.6846, -9.4859) (-2.5829, -9.4705) (-2.4817, -9.459) (-2.3813, -9.4534) (-2.2825, -9.4558) (-2.1859, -9.4677) (-2.0922, -9.4901) (-2.0018, -9.5235) (-1.9149, -9.5673) (-1.8314, -9.6203) (-1.751, -9.6806) (-1.6733, -9.7464) (-1.5973, -9.8157) (-1.5221, -9.8868) (-1.4467, -9.9581) (-1.3701, -10.0281) (-1.2913, -10.0951) (-1.2095, -10.1575) (-1.1244, -10.2133) (-1.0358, -10.2604) (-0.9439, -10.2973) (-0.8489, -10.3225) (-0.7516, -10.3355) (-0.6525, -10.3367) (-0.5526, -10.327) (-0.4526, -10.3081) (-0.3532, -10.2817) (-0.2547, -10.25) (-0.1572, -10.2146) (-0.0602, -10.1776) (0.0364, -10.1406) (0.1331, -10.1057) (0.2302, -10.0747) (0.3275, -10.0497) (0.4249, -10.0327) (0.5219, -10.0255) (0.6182, -10.0293) (0.7134, -10.0444) (0.8072, -10.0704) (0.8994, -10.106) (0.99, -10.1495) (1.0791, -10.1989) (1.1671, -10.252) (1.2547, -10.3071) (1.3426, -10.3623) (1.4314, -10.416) (1.5218, -10.4664) (1.6142, -10.5116) (1.7085, -10.5497) (1.8046, -10.5787) (1.902, -10.5969) (2, -10.6031) (2.098, -10.5969) (2.1954, -10.5787) (2.2915, -10.5497) (2.3858, -10.5116) (2.4782, -10.4664) (2.5686, -10.416) (2.6574, -10.3623) (2.7453, -10.3071) (2.8329, -10.252) (2.9209, -10.1989) (3.01, -10.1495) (3.1006, -10.106) (3.1928, -10.0704) (3.2866, -10.0444) (3.3818, -10.0293) (3.4781, -10.0255) (3.5751, -10.0327) (3.6725, -10.0497) (3.7698, -10.0747) (3.8669, -10.1057) (3.9636, -10.1406) (4.0602, -10.1776) (4.1572, -10.2146) (4.2547, -10.25) (4.3532, -10.2817) (4.4526, -10.3081) (4.5526, -10.327) (4.6525, -10.3367) (4.7516, -10.3355) (4.8489, -10.3225) (4.9439, -10.2973) (5.0358, -10.2604) (5.1244, -10.2133) (5.2095, -10.1575) (5.2913, -10.0951) (5.3701, -10.0281) (5.4467, -9.9581) (5.5221, -9.8868) (5.5973, -9.8157) (5.6733, -9.7464) (5.751, -9.6806) (5.8314, -9.6203) (5.9149, -9.5673) (6.0018, -9.5235) (6.0922, -9.4901) (6.1859, -9.4677) (6.2825, -9.4558) (6.3813, -9.4534) (6.4817, -9.459) (6.5829, -9.4705) (6.6846, -9.4859) (6.7865, -9.5032) (6.8888, -9.5207) (6.9914, -9.5363) (7.0942, -9.5482) (7.1969, -9.5547) (7.2986, -9.5537) (7.3985, -9.5437) (7.4954, -9.5233) (7.5884, -9.4915) (7.6766, -9.4482) (7.7596, -9.3942) (7.8372, -9.3306) (7.9098, -9.2593) (7.9779, -9.1822) (8.0421, -9.1011) (8.1036, -9.0175) (8.1636, -8.9328) (8.2235, -8.8484) (8.2845, -8.7656) (8.3479, -8.6859) (8.415, -8.6111) (8.4865, -8.5429) (8.5632, -8.483) (8.6453, -8.4326) (8.7329, -8.3923) (8.8253, -8.3618) (8.9218, -8.3402) (9.0213, -8.326) (9.1228, -8.3176) (9.2255, -8.3128) (9.3289, -8.31) (9.4327, -8.3071) (9.5363, -8.3024) (9.6395, -8.2941) (9.7414, -8.2803) (9.841, -8.2596) (9.937, -8.2303) (10.0281, -8.1913) (10.113, -8.142) (10.1911, -8.0824) (10.262, -8.0132) (10.3258, -7.9357) (10.3831, -7.8516) (10.4347, -7.7627) (10.4819, -7.6706) (10.5259, -7.5766) (10.5683, -7.4819) (10.6105, -7.3874) (10.6542, -7.2943) (10.7009, -7.2038) (10.752, -7.1173) (10.8089, -7.0364) (10.8724, -6.9627) (10.9431, -6.8972) (11.0212, -6.8406) (11.1059, -6.7927) (11.1962, -6.7527) (11.291, -6.7194) (11.3889, -6.6913) (11.4888, -6.6666) (11.5897, -6.6436) (11.6908, -6.6206) (11.7916, -6.5957) (11.8911, -6.5674) (11.9884, -6.5341) (12.0821, -6.4943) (12.1705, -6.4469) (12.2522, -6.3909) (12.326, -6.326) (12.3909, -6.2522) (12.4469, -6.1705) (12.4943, -6.0821) (12.5341, -5.9884) (12.5674, -5.8911) (12.5957, -5.7916) (12.6206, -5.6908) (12.6436, -5.5897) (12.6666, -5.4888) (12.6913, -5.3889) (12.7194, -5.291) (12.7527, -5.1962) (12.7927, -5.1059) (12.8406, -5.0212) (12.8972, -4.9431) (12.9627, -4.8724) (13.0364, -4.8089) (13.1173, -4.752) (13.2038, -4.7009) (13.2943, -4.6542) (13.3874, -4.6105) (13.4819, -4.5683) (13.5766, -4.5259) (13.6706, -4.4819) (13.7627, -4.4347) (13.8516, -4.3831) (13.9357, -4.3258) (14.0132, -4.262) (14.0824, -4.1911) (14.142, -4.113) (14.1913, -4.0281) (14.2303, -3.937) (14.2596, -3.841) (14.2803, -3.7414) (14.2941, -3.6395) (14.3024, -3.5363) (14.3071, -3.4327) (14.31, -3.3289) (14.3128, -3.2255) (14.3176, -3.1228) (14.326, -3.0213) (14.3402, -2.9218) (14.3618, -2.8253) (14.3923, -2.7329) (14.4326, -2.6453) (14.483, -2.5632) (14.5429, -2.4865) (14.6111, -2.415) (14.6859, -2.3479) (14.7656, -2.2845) (14.8484, -2.2235) (14.9328, -2.1636) (15.0175, -2.1036) (15.1011, -2.0421) (15.1822, -1.9779) (15.2593, -1.9098) (15.3306, -1.8372) (15.3942, -1.7596) (15.4482, -1.6766) (15.4915, -1.5884) (15.5233, -1.4954) (15.5437, -1.3985) (15.5537, -1.2986) (15.5547, -1.1969) (15.5482, -1.0942) (15.5363, -0.9914) (15.5207, -0.8888) (15.5032, -0.7865) (15.4859, -0.6846) (15.4705, -0.5829) (15.459, -0.4817) (15.4534, -0.3813) (15.4558, -0.2825) (15.4677, -0.1859) (15.4901, -0.0922) (15.5235, -0.0018) (15.5673, 0.0851) (15.6203, 0.1686) (15.6806, 0.249) (15.7464, 0.3267) (15.8157, 0.4027) (15.8868, 0.4779) (15.9581, 0.5533) (16.0281, 0.6299) (16.0951, 0.7087) (16.1575, 0.7905) (16.2133, 0.8756) (16.2604, 0.9642) (16.2973, 1.0561) (16.3225, 1.1511) (16.3355, 1.2484) (16.3367, 1.3475) (16.327, 1.4474) (16.3081, 1.5474) (16.2817, 1.6468) (16.25, 1.7453) (16.2146, 1.8428) (16.1776, 1.9398) (16.1406, 2.0364) (16.1057, 2.1331) (16.0747, 2.2302) (16.0497, 2.3275) (16.0327, 2.4249) (16.0255, 2.5219) (16.0293, 2.6182) (16.0444, 2.7134) (16.0704, 2.8072) (16.106, 2.8994) (16.1495, 2.99) (16.1989, 3.0791) (16.252, 3.1671) (16.3071, 3.2547) (16.3623, 3.3426) (16.416, 3.4314) (16.4664, 3.5218) (16.5116, 3.6142) (16.5497, 3.7085) (16.5787, 3.8046) (16.5932, 3.8825) (16.5988, 3.9412) (16.6, 3.9804) (16.6, 4) knots 0 0 0 0 0 0 0.00104167 0.00208333 0.003125 0.00416667 0.00520833 0.00625 0.00729167 0.00833333 0.009375 0.01041667 0.01145833 0.0125 0.01354167 0.01458333 0.015625 0.01666667 0.01770833 0.01875 0.01979167 0.02083333 0.021875 0.02291667 0.02395833 0.025 0.02604167 0.02708333 0.028125 0.02916667 0.03020833 0.03125 0.03229167 0.03333333 0.034375 0.03541667 0.03645833 0.0375 0.03854167 0.03958333 0.040625 0.04166667 0.04270833 0.04375 0.04479167 0.04583333 0.046875 0.04791667 0.04895833 0.05 0.05104167 0.05208333 0.053125 0.05416667 0.05520833 0.05625 0.05729167 0.05833333 0.059375 0.06041667 0.06145833 0.0625 0.06354167 0.06458333 0.065625 0.06666667 0.06770833 0.06875 0.06979167 0.07083333 0.071875 0.07291667 0.07395833 0.075 0.07604167 0.07708333 0.078125 0.07916667 0.08020833 0.08125 0.08229167 0.08333333 0.084375 0.08541667 0.08645833 0.0875 0.08854167 0.08958333 0.090625 0.09166667 0.09270833 0.09375 0.09479167 0.09583333 0.096875 0.09791667 0.09895833 0.1 0.10104167 0.10208333 0.103125 0.10416667 0.10520833 0.10625 0.10729167 0.10833333 0.109375 0.11041667 0.11145833 0.1125 0.11354167 0.11458333 0.115625 0.11666667 0.11770833 0.11875 0.11979167 0.12083333 0.121875 0.12291667 0.12395833 0.125 0.12604167 0.12708333 0.128125 0.12916667 0.13020833 0.13125 0.13229167 0.13333333 0.134375 0.13541667 0.13645833 0.1375 0.13854167 0.13958333 0.140625 0.14166667 0.14270833 0.14375 0.14479167 0.14583333 0.146875 0.14791667 0.14895833 0.15 0.15104167 0.15208333 0.153125 0.15416667 0.15520833 0.15625 0.15729167 0.15833333 0.159375 0.16041667 0.16145833 0.1625 0.16354167 0.16458333 0.165625 0.16666667 0.16770833 0.16875 0.16979167 0.17083333 0.171875 0.17291667 0.17395833 0.175 0.17604167 0.17708333 0.178125 0.17916667 0.18020833 0.18125 0.18229167 0.18333333 0.184375 0.18541667 0.18645833 0.1875 0.18854167 0.18958333 0.190625 0.19166667 0.19270833 0.19375 0.19479167 0.19583333 0.196875 0.19791667 0.19895833 0.2 0.20104167 0.20208333 0.203125 0.20416667 0.20520833 0.20625 0.20729167 0.20833333 0.209375 0.21041667 0.21145833 0.2125 0.21354167 0.21458333 0.215625 0.21666667 0.21770833 0.21875 0.21979167 0.22083333 0.221875 0.22291667 0.22395833 0.225 0.22604167 0.22708333 0.228125 0.22916667 0.23020833 0.23125 0.23229167 0.23333333 0.234375 0.23541667 0.23645833 0.2375 0.23854167 0.23958333 0.240625 0.24166667 0.24270833 0.24375 0.24479167 0.24583333 0.246875 0.24791667 0.24895833 0.25 0.25104167 0.25208333 0.253125 0.25416667 0.25520833 0.25625 0.25729167 0.25833333 0.259375 0.26041667 0.26145833 0.2625 0.26354167 0.26458333 0.265625 0.26666667 0.26770833 0.26875 0.26979167 0.27083333 0.271875 0.27291667 0.27395833 0.275 0.27604167 0.27708333 0.278125 0.27916667 0.28020833 0.28125 0.28229167 0.28333333 0.284375 0.28541667 0.28645833 0.2875 0.28854167 0.28958333 0.290625 0.29166667 0.29270833 0.29375 0.29479167 0.29583333 0.296875 0.29791667 0.29895833 0.3 0.30104167 0.30208333 0.303125 0.30416667 0.30520833 0.30625 0.30729167 0.30833333 0.309375 0.31041667 0.31145833 0.3125 0.31354167 0.31458333 0.315625 0.31666667 0.31770833 0.31875 0.31979167 0.32083333 0.321875 0.32291667 0.32395833 0.325 0.32604167 0.32708333 0.328125 0.32916667 0.33020833 0.33125 0.33229167 0.33333333 0.334375 0.33541667 0.33645833 0.3375 0.33854167 0.33958333 0.340625 0.34166667 0.34270833 0.34375 0.34479167 0.34583333 0.346875 0.34791667 0.34895833 0.35 0.35104167 0.35208333 0.353125 0.35416667 0.35520833 0.35625 0.35729167 0.35833333 0.359375 0.36041667 0.36145833 0.3625 0.36354167 0.36458333 0.365625 0.36666667 0.36770833 0.36875 0.36979167 0.37083333 0.371875 0.37291667 0.37395833 0.375 0.37604167 0.37708333 0.378125 0.37916667 0.38020833 0.38125 0.38229167 0.38333333 0.384375 0.38541667 0.38645833 0.3875 0.38854167 0.38958333 0.390625 0.39166667 0.39270833 0.39375 0.39479167 0.39583333 0.396875 0.39791667 0.39895833 0.4 0.40104167 0.40208333 0.403125 0.40416667 0.40520833 0.40625 0.40729167 0.40833333 0.409375 0.41041667 0.41145833 0.4125 0.41354167 0.41458333 0.415625 0.41666667 0.41770833 0.41875 0.41979167 0.42083333 0.421875 0.42291667 0.42395833 0.425 0.42604167 0.42708333 0.428125 0.42916667 0.43020833 0.43125 0.43229167 0.43333333 0.434375 0.43541667 0.43645833 0.4375 0.43854167 0.43958333 0.440625 0.44166667 0.44270833 0.44375 0.44479167 0.44583333 0.446875 0.44791667 0.44895833 0.45 0.45104167 0.45208333 0.453125 0.45416667 0.45520833 0.45625 0.45729167 0.45833333 0.459375 0.46041667 0.46145833 0.4625 0.46354167 0.46458333 0.465625 0.46666667 0.46770833 0.46875 0.46979167 0.47083333 0.471875 0.47291667 0.47395833 0.475 0.47604167 0.47708333 0.478125 0.47916667 0.48020833 0.48125 0.48229167 0.48333333 0.484375 0.48541667 0.48645833 0.4875 0.48854167 0.48958333 0.490625 0.49166667 0.49270833 0.49375 0.49479167 0.49583333 0.496875 0.49791667 0.49895833 0.5 0.50104167 0.50208333 0.503125 0.50416667 0.50520833 0.50625 0.50729167 0.50833333 0.509375 0.51041667 0.51145833 0.5125 0.51354167 0.51458333 0.515625 0.51666667 0.51770833 0.51875 0.51979167 0.52083333 0.521875 0.52291667 0.52395833 0.525 0.52604167 0.52708333 0.528125 0.52916667 0.53020833 0.53125 0.53229167 0.53333333 0.534375 0.53541667 0.53645833 0.5375 0.53854167 0.53958333 0.540625 0.54166667 0.54270833 0.54375 0.54479167 0.54583333 0.546875 0.54791667 0.54895833 0.55 0.55104167 0.55208333 0.553125 0.55416667 0.55520833 0.55625 0.55729167 0.55833333 0.559375 0.56041667 0.56145833 0.5625 0.56354167 0.56458333 0.565625 0.56666667 0.56770833 0.56875 0.56979167 0.57083333 0.571875 0.57291667 0.57395833 0.575 0.57604167 0.57708333 0.578125 0.57916667 0.58020833 0.58125 0.58229167 0.58333333 0.584375 0.58541667 0.58645833 0.5875 0.58854167 0.58958333 0.590625 0.59166667 0.59270833 0.59375 0.59479167 0.59583333 0.596875 0.59791667 0.59895833 0.6 0.60104167 0.60208333 0.603125 0.60416667 0.60520833 0.60625 0.60729167 0.60833333 0.609375 0.61041667 0.61145833 0.6125 0.61354167 0.61458333 0.615625 0.61666667 0.61770833 0.61875 0.61979167 0.62083333 0.621875 0.62291667 0.62395833 0.625 0.62604167 0.62708333 0.628125 0.62916667 0.63020833 0.63125 0.63229167 0.63333333 0.634375 0.63541667 0.63645833 0.6375 0.63854167 0.63958333 0.640625 0.64166667 0.64270833 0.64375 0.64479167 0.64583333 0.646875 0.64791667 0.64895833 0.65 0.65104167 0.65208333 0.653125 0.65416667 0.65520833 0.65625 0.65729167 0.65833333 0.659375 0.66041667 0.66145833 0.6625 0.66354167 0.66458333 0.665625 0.66666667 0.66770833 0.66875 0.66979167 0.67083333 0.671875 0.67291667 0.67395833 0.675 0.67604167 0.67708333 0.678125 0.67916667 0.68020833 0.68125 0.68229167 0.68333333 0.684375 0.68541667 0.68645833 0.6875 0.68854167 0.68958333 0.690625 0.69166667 0.69270833 0.69375 0.69479167 0.69583333 0.696875 0.69791667 0.69895833 0.7 0.70104167 0.70208333 0.703125 0.70416667 0.70520833 0.70625 0.70729167 0.70833333 0.709375 0.71041667 0.71145833 0.7125 0.71354167 0.71458333 0.715625 0.71666667 0.71770833 0.71875 0.71979167 0.72083333 0.721875 0.72291667 0.72395833 0.725 0.72604167 0.72708333 0.728125 0.72916667 0.73020833 0.73125 0.73229167 0.73333333 0.734375 0.73541667 0.73645833 0.7375 0.73854167 0.73958333 0.740625 0.74166667 0.74270833 0.74375 0.74479167 0.74583333 0.746875 0.74791667 0.74895833 0.75 0.75104167 0.75208333 0.753125 0.75416667 0.75520833 0.75625 0.75729167 0.75833333 0.759375 0.76041667 0.76145833 0.7625 0.76354167 0.76458333 0.765625 0.76666667 0.76770833 0.76875 0.76979167 0.77083333 0.771875 0.77291667 0.77395833 0.775 0.77604167 0.77708333 0.778125 0.77916667 0.78020833 0.78125 0.78229167 0.78333333 0.784375 0.78541667 0.78645833 0.7875 0.78854167 0.78958333 0.790625 0.79166667 0.79270833 0.79375 0.79479167 0.79583333 0.796875 0.79791667 0.79895833 0.8 0.80104167 0.80208333 0.803125 0.80416667 0.80520833 0.80625 0.80729167 0.80833333 0.809375 0.81041667 0.81145833 0.8125 0.81354167 0.81458333 0.815625 0.81666667 0.81770833 0.81875 0.81979167 0.82083333 0.821875 0.82291667 0.82395833 0.825 0.82604167 0.82708333 0.828125 0.82916667 0.83020833 0.83125 0.83229167 0.83333333 0.834375 0.83541667 0.83645833 0.8375 0.83854167 0.83958333 0.840625 0.84166667 0.84270833 0.84375 0.84479167 0.84583333 0.846875 0.84791667 0.84895833 0.85 0.85104167 0.85208333 0.853125 0.85416667 0.85520833 0.85625 0.85729167 0.85833333 0.859375 0.86041667 0.86145833 0.8625 0.86354167 0.86458333 0.865625 0.86666667 0.86770833 0.86875 0.86979167 0.87083333 0.871875 0.87291667 0.87395833 0.875 0.87604167 0.87708333 0.878125 0.87916667 0.88020833 0.88125 0.88229167 0.88333333 0.884375 0.88541667 0.88645833 0.8875 0.88854167 0.88958333 0.890625 0.89166667 0.89270833 0.89375 0.89479167 0.89583333 0.896875 0.89791667 0.89895833 0.9 0.90104167 0.90208333 0.903125 0.90416667 0.90520833 0.90625 0.90729167 0.90833333 0.909375 0.91041667 0.91145833 0.9125 0.91354167 0.91458333 0.915625 0.91666667 0.91770833 0.91875 0.91979167 0.92083333 0.921875 0.92291667 0.92395833 0.925 0.92604167 0.92708333 0.928125 0.92916667 0.93020833 0.93125 0.93229167 0.93333333 0.934375 0.93541667 0.93645833 0.9375 0.93854167 0.93958333 0.940625 0.94166667 0.94270833 0.94375 0.94479167 0.94583333 0.946875 0.94791667 0.94895833 0.95 0.95104167 0.95208333 0.953125 0.95416667 0.95520833 0.95625 0.95729167 0.95833333 0.959375 0.96041667 0.96145833 0.9625 0.96354167 0.96458333 0.965625 0.96666667 0.96770833 0.96875 0.96979167 0.97083333 0.971875 0.97291667 0.97395833 0.975 0.97604167 0.97708333 0.978125 0.97916667 0.98020833 0.98125 0.98229167 0.98333333 0.984375 0.98541667 0.98645833 0.9875 0.98854167 0.98958333 0.990625 0.99166667 0.99270833 0.99375 0.99479167 0.99583333 0.996875 0.99791667 0.99895833 1 1 1 1 1 1
  point P0 (16.4672, 4.4736)
  point P1 (16.1945, 4.9304)
  point P2 (16.0321, 5.382)
  point P3 (16.1033, 5.8567)
  point P4 (16.2817, 6.3579)
  point P5 (16.3195, 6.8483)
  point P6 (16.0969, 7.2869)
  point P7 (15.7403, 7.6817)
  point P8 (15.4929, 8.093)
  point P9 (15.4701, 8.5725)
  point P10 (15.5472, 9.0988)
  point P11 (15.4886, 9.5872)
  point P12 (15.1848, 9.9739)
  point P13 (14.758, 10.2916)
  point P14 (14.4351, 10.6467)
  point P15 (14.3192, 11.1125)
  point P16 (14.2922, 11.6438)
  point P17 (14.1395, 12.1113)
  point P18 (13.766, 12.4314)
  point P19 (13.2855, 12.6596)
  point P20 (12.8994, 12.9449)
  point P21 (12.6949, 13.3792)
  point P22 (12.5648, 13.895)
  point P23 (12.3238, 14.3238)
  point P24 (11.895, 14.5648)
  point P25 (11.3792, 14.6949)
  point P26 (10.9449, 14.8994)
  point P27 (10.6596, 15.2855)
  point P28 (10.4314, 15.766)
  point P29 (10.1113, 16.1395)
  point P30 (9.6438, 16.2922)
  point P31 (9.1125, 16.3192)
  point P32 (8.6467, 16.4351)
  point P33 (8.2916, 16.758)
  point P34 (7.9739, 17.1848)
  point P35 (7.5872, 17.4886)
  point P36 (7.0988, 17.5472)
  point P37 (6.5725, 17.4701)
  point P38 (6.093, 17.4929)
  point P39 (5.6817, 17.7403)
  point P40 (5.2869, 18.0969)
  point P41 (4.8483, 18.3195)
  point P42 (4.3579, 18.2817)
  point P43 (3.8567, 18.1033)
  point P44 (3.382, 18.0321)
  point P45 (2.9304, 18.1945)
  point P46 (2.4736, 18.4672)
  point P47 (2, 18.6)
  point P48 (1.5264, 18.4672)
  point P49 (1.0696, 18.1945)
  point P50 (0.618, 18.0321)
  point P51 (0.1433, 18.1033)
  point P52 (-0.3579, 18.2817)
  point P53 (-0.8483, 18.3195)
  point P54 (-1.2869, 18.0969)
  point P55 (-1.6817, 17.7403)
  point P56 (-2.093, 17.4929)
  point P57 (-2.5725, 17.4701)
  point P58 (-3.0988, 17.5472)
  point P59 (-3.5872, 17.4886)
  point P60 (-3.9739, 17.1848)
  point P61 (-4.2916, 16.758)
  point P62 (-4.6467, 16.4351)
  point P63 (-5.1125, 16.3192)
  point P64 (-5.6438, 16.2922)
  point P65 (-6.1113, 16.1395)
  point P66 (-6.4314, 15.766)
  point P67 (-6.6596, 15.2855)
  point P68 (-6.9449, 14.8994)
  point P69 (-7.3792, 14.6949)
  point P70 (-7.895, 14.5648)
  point P71 (-8.3238, 14.3238)
  point P72 (-8.5648, 13.895)
  point P73 (-8.6949, 13.3792)
  point P74 (-8.8994, 12.9449)
  point P75 (-9.2855, 12.6596)
  point P76 (-9.766, 12.4314)
  point P77 (-10.1395, 12.1113)
  point P78 (-10.2922, 11.6438)
  point P79 (-10.3192, 11.1125)
  point P80 (-10.4351, 10.6467)
  point P81 (-10.758, 10.2916)
  point P82 (-11.1848, 9.9739)
  point P83 (-11.4886, 9.5872)
  point P84 (-11.5472, 9.0988)
  point P85 (-11.4701, 8.5725)
  point P86 (-11.4929, 8.093)
  point P87 (-11.7403, 7.6817)
  point P88 (-12.0969, 7.2869)
  point P89 (-12.3195, 6.8483)
  point P90 (-12.2817, 6.3579)
  point P91 (-12.1033, 5.8567)
  point P92 (-12.0321, 5.382)
  point P93 (-12.1945, 4.9304)
  point P94 (-12.4672, 4.4736)
  point P95 (-12.6, 4)
  point P96 (-12.4672, 3.5264)
  point P97 (-12.1945, 3.0696)
  point P98 (-12.0321, 2.618)
  point P99 (-12.1033, 2.1433)
  point P100 (-12.2817, 1.6421)
  point P101 (-12.3195, 1.1517)
  point P102 (-12.0969, 0.7131)
  point P103 (-11.7403, 0.3183)
  point P104 (-11.4929, -0.093)
  point P105 (-11.4701, -0.5725)
  point P106 (-11.5472, -1.0988)